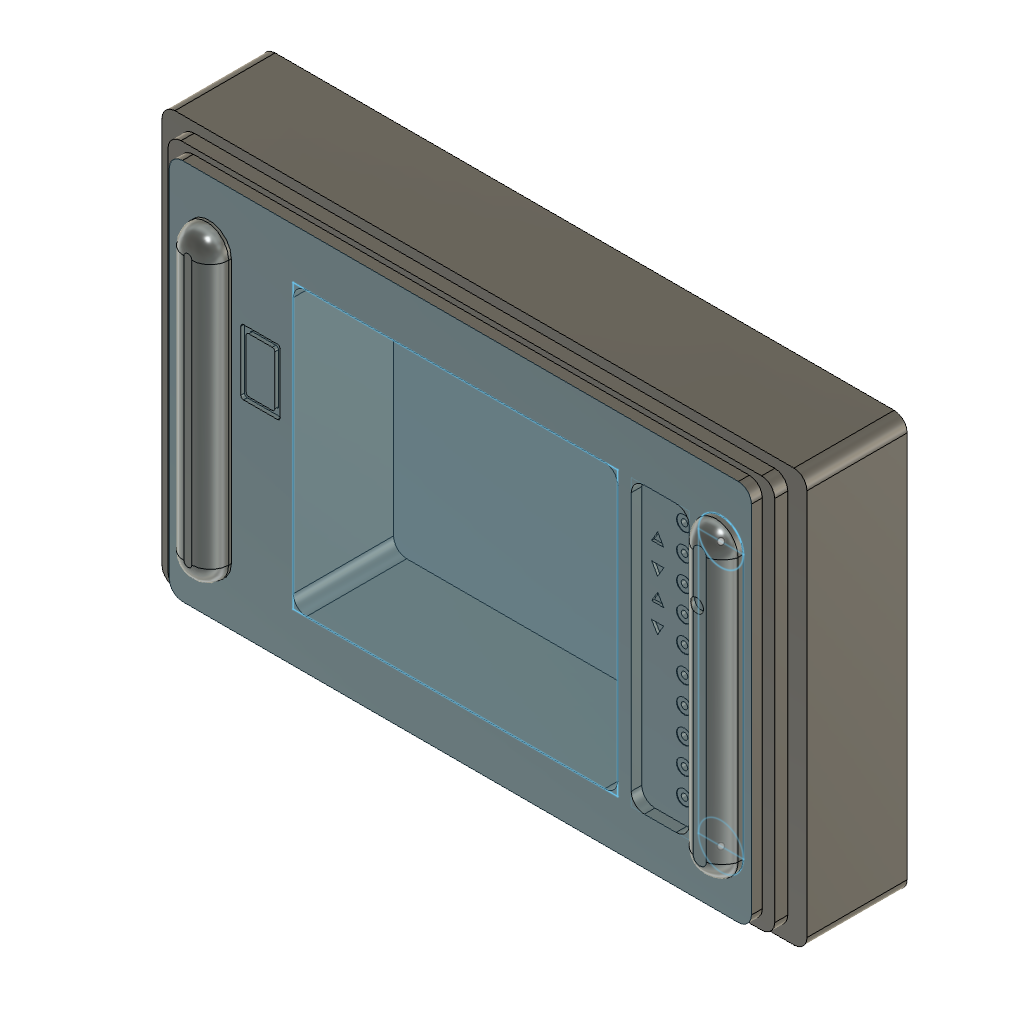
radar 5 (Autodesk Fusion 360 design; units mm, degrees)
part number: 2026-11-02-20-23-44-263
Autodesk Fusion 360 part; units mm, degrees
sketch "screen" plane through (0, 0, 0) normal (0, 1, 0) x (1, 0, 0)
  line L0 (-50.0347, -23.9941) -> (11.4653, -23.9941)
  line L1 (11.4653, -23.9941) -> (11.4653, 29.6059)
  line L2 (11.4653, 29.6059) -> (-50.0347, 29.6059)
  line L3 (-50.0347, 29.6059) -> (-50.0347, -23.9941)
  dimension "d1" = 61.5
  dimension "d2" = 53.6
  constraint horizontal L0
  constraint vertical L1
  constraint horizontal L2
  constraint vertical L3
  measures "d1" distance of L0.start L0.end
  measures "d2" distance of L0.start L2.end
sketch "shell" plane through (0, 0, 0) normal (0, 1, 0) x (-1, 0, 0)
  line L0 (86.0395, 43.9923) -> (-47.4605, 43.9923)
  line L1 (-47.4605, 43.9923) -> (-47.4605, -43.6077)
  line L2 (-47.4605, -43.6077) -> (86.0395, -43.6077)
  line L3 (86.0395, -43.6077) -> (86.0395, 43.9923)
  dimension "d3" = 133.5
  dimension "d4" = 87.6
  constraint horizontal L0
  constraint vertical L1
  constraint horizontal L2
  constraint vertical L3
  measures "d3" distance of L0.start L0.end
  measures "d4" distance of L0.start L2.end
extrude "Extrude1" add sketch "shell" along normal blind 2.5
sketch "1st shell extrude" plane through (0, 2.5, 0) normal (0, 1, 0) x (-1, 0, 0)
  line L0 (86.0395, -43.6077) -> (86.0395, 43.9923)
  line L1 (86.0395, 43.9923) -> (-47.4605, 43.9923)
  line L2 (-47.4605, 43.9923) -> (-47.4605, -43.6077)
  line L3 (-47.4605, -43.6077) -> (86.0395, -43.6077)
  line L4 (-50.2932, 45.2731) -> (88.8398, 45.2731)
  line L5 (88.8398, 45.2731) -> (88.8398, -44.9576)
  line L6 (88.8398, -44.9576) -> (-50.2932, -44.9576)
  line L7 (-50.2932, -44.9576) -> (-50.2932, 45.2731)
  constraint horizontal L4
  constraint vertical L5
  constraint horizontal L6
  constraint vertical L7
extrude "Extrude2" add sketch "1st shell extrude" along normal blind 3 contours L0 L1 L2 L3 | L4 L5 L6 L7
sketch "2nd shell extrude" plane through (0, 5.5, 0) normal (0, 1, 0) x (-1, 0, 0)
  line L0 (-50.2932, -44.9576) -> (88.8398, -44.9576)
  line L1 (88.8398, -44.9576) -> (88.8398, 45.2731)
  line L2 (88.8398, 45.2731) -> (-50.2932, 45.2731)
  line L3 (-50.2932, 45.2731) -> (-50.2932, -44.9576)
  line L4 (-54.7046, 47.5235) -> (93.2505, 47.5235)
  line L5 (93.2505, 47.5235) -> (93.2505, -47.2096)
  line L6 (93.2505, -47.2096) -> (-54.7046, -47.2096)
  line L7 (-54.7046, -47.2096) -> (-54.7046, 47.5235)
  constraint horizontal L4
  constraint vertical L5
  constraint horizontal L6
  constraint vertical L7
extrude "Extrude3" add sketch "2nd shell extrude" along normal blind 23 contours L0 L1 L2 L3 | L4 L5 L6 L7
fillet "Fillet1" radius 3 12 edges at (47.4605, 1.25, 43.9923) (50.2932, 4, 45.2731) (54.7046, 17, 47.5235) (54.7046, 17, -47.2096) (50.2932, 4, -44.9576) (47.4605, 1.25, -43.6077) (-86.0395, 1.25, 43.9923) (-88.8398, 4, 45.2731) (-93.2505, 17, 47.5235) (-93.2505, 17, -47.2096) (-88.8398, 4, -44.9576) (-86.0395, 1.25, -43.6077)
scale "Scale1" factor 0.826235 about (-83.0395, 0, 43.9923) bodies 1
move_body "Move1" bodies 1 to x (1, 0, 0) y (0, 1, 0) z (0, 0, 1) at (12, 0, -9.5)
move_body "Move2" bodies 1 to x (1, 0, 0) y (0, 1, 0) z (0, 0, 1) at (0, 0, -1)
extrude "Extrude11" cut sketch "screen" along normal blind 19
fillet "Fillet6" radius 2.5 4 edges at (-50.0347, 9.5, -29.6059) (11.4653, 9.5, -29.6059) (11.4653, 9.5, 23.9941) (-50.0347, 9.5, 23.9941)
sketch "Sketch16" plane through (0, 0, 0) normal (0, -1, 0) x (1, 0, 0)
  line L0 (8.9653, -29.6059) -> (-47.5347, -29.6059)
  arc A0 (-50.0347, -27.1059) -> (-47.5347, -29.6059) centre (-47.5347, -27.1059) ccw
  line L1 (-50.0347, -27.1059) -> (-50.0347, 21.4941)
  arc A1 (-47.5347, 23.9941) -> (-50.0347, 21.4941) centre (-47.5347, 21.4941) ccw
  line L2 (-47.5347, 23.9941) -> (8.9653, 23.9941)
  arc A2 (11.4653, 21.4941) -> (8.9653, 23.9941) centre (8.9653, 21.4941) ccw
  line L3 (11.4653, 21.4941) -> (11.4653, -27.1059)
  arc A3 (8.9653, -29.6059) -> (11.4653, -27.1059) centre (8.9653, -27.1059) ccw
  arc A4 (-73.5182, -36.4072) -> (-71.0395, -38.8859) centre (-71.0395, -36.4072) ccw
  line L4 (-71.0395, -38.8859) -> (34.3055, -38.8859)
  arc A5 (34.3055, -38.8859) -> (36.7842, -36.4072) centre (34.3055, -36.4072) ccw
  line L5 (36.7842, -36.4072) -> (36.7842, 31.0136)
  arc A6 (36.7842, 31.0136) -> (34.3055, 33.4923) centre (34.3055, 31.0136) ccw
  line L6 (34.3055, 33.4923) -> (-71.0395, 33.4923)
  arc A7 (-71.0395, 33.4923) -> (-73.5182, 31.0136) centre (-71.0395, 31.0136) ccw
  line L7 (-73.5182, 31.0136) -> (-73.5182, -36.4072)
  line L8 (14, 24) -> (25, 24)
  line L9 (25, 24) -> (25, -30)
  line L10 (25, -30) -> (14, -30)
  line L11 (14, -30) -> (14, 24)
  constraint horizontal L8
  constraint vertical L9
  constraint horizontal L10
  constraint vertical L11
extrude "Extrude12" cut sketch "Sketch16" against normal blind 2 contours L8 L9 L10 L11
sketch "Sketch17" plane through (0, 0, 0) normal (0, -1, 0) x (1, 0, 0)
  line L0 (25, 24) -> (25, -30)
  line L1 (25, -30) -> (14, -30)
  line L2 (14, -30) -> (14, 24)
  line L3 (14, 24) -> (25, 24)
  line L4 (8.9653, -29.6059) -> (-47.5347, -29.6059)
  arc A0 (-50.0347, -27.1059) -> (-47.5347, -29.6059) centre (-47.5347, -27.1059) ccw
  line L5 (-50.0347, -27.1059) -> (-50.0347, 21.4941)
  arc A1 (-47.5347, 23.9941) -> (-50.0347, 21.4941) centre (-47.5347, 21.4941) ccw
  line L6 (-47.5347, 23.9941) -> (8.9653, 23.9941)
  arc A2 (11.4653, 21.4941) -> (8.9653, 23.9941) centre (8.9653, 21.4941) ccw
  line L7 (11.4653, 21.4941) -> (11.4653, -27.1059)
  arc A3 (8.9653, -29.6059) -> (11.4653, -27.1059) centre (8.9653, -27.1059) ccw
  arc A4 (-73.5182, -36.4072) -> (-71.0395, -38.8859) centre (-71.0395, -36.4072) ccw
  line L8 (-71.0395, -38.8859) -> (34.3055, -38.8859)
  arc A5 (34.3055, -38.8859) -> (36.7842, -36.4072) centre (34.3055, -36.4072) ccw
  line L9 (36.7842, -36.4072) -> (36.7842, 31.0136)
  arc A6 (36.7842, 31.0136) -> (34.3055, 33.4923) centre (34.3055, 31.0136) ccw
  line L10 (34.3055, 33.4923) -> (-71.0395, 33.4923)
  arc A7 (-71.0395, 33.4923) -> (-73.5182, 31.0136) centre (-71.0395, 31.0136) ccw
  line L11 (-73.5182, 31.0136) -> (-73.5182, -36.4072)
  circle A8 centre (31, 22) radius 4.2426
  circle A9 centre (31, -28) radius 4.2426
  line L12 (26.7574, 22) -> (35.2426, 22)
  line L13 (35.2426, 22) -> (35.2426, -28)
  line L14 (35.2426, -28) -> (26.7574, -28)
  line L15 (26.7574, -28) -> (26.7574, 22)
  circle A10 centre (31, 22) radius 4.2426
  constraint horizontal L12
  constraint vertical L13
  constraint horizontal L14
  constraint vertical L15
  constraint coincident A9 L13.end
  constraint coincident A8 L12.start
  constraint concentric A8 A10
extrude "Extrude13" add sketch "Sketch17" along normal blind 4 contours A8 L12 A10 | A8 A9 L13 L15 A10 | A8 L12 A10 | A9 L14 | A9 L14
fillet "Fillet7" radius 3 tangency weight 0.49828 4 edges at (26.7574, -4, -3) (31, -4, -32.2426) (35.2426, -4, -3) (31, -4, 26.2426)
sketch "Sketch18" plane through (0, 0, 0) normal (0, -1, 0) x (1, 0, 0)
  line L0 (35.2426, 22) -> (35.2426, -28)
  arc A0 (26.7574, -28) -> (35.2426, -28) centre (31, -28) ccw
  line L1 (26.7574, -28) -> (26.7574, 22)
  arc A1 (35.2426, 22) -> (26.7574, 22) centre (31, 22) ccw
  line L2 (25, 24) -> (25, -30)
  line L3 (25, -30) -> (14, -30)
  line L4 (14, -30) -> (14, 24)
  line L5 (14, 24) -> (25, 24)
  line L6 (8.9653, -29.6059) -> (-47.5347, -29.6059)
  arc A2 (-50.0347, -27.1059) -> (-47.5347, -29.6059) centre (-47.5347, -27.1059) ccw
  line L7 (-50.0347, -27.1059) -> (-50.0347, 21.4941)
  arc A3 (-47.5347, 23.9941) -> (-50.0347, 21.4941) centre (-47.5347, 21.4941) ccw
  line L8 (-47.5347, 23.9941) -> (8.9653, 23.9941)
  arc A4 (11.4653, 21.4941) -> (8.9653, 23.9941) centre (8.9653, 21.4941) ccw
  line L9 (11.4653, 21.4941) -> (11.4653, -27.1059)
  arc A5 (8.9653, -29.6059) -> (11.4653, -27.1059) centre (8.9653, -27.1059) ccw
  arc A6 (-73.5182, -36.4072) -> (-71.0395, -38.8859) centre (-71.0395, -36.4072) ccw
  line L10 (-71.0395, -38.8859) -> (34.3055, -38.8859)
  arc A7 (34.3055, -38.8859) -> (36.7842, -36.4072) centre (34.3055, -36.4072) ccw
  line L11 (36.7842, -36.4072) -> (36.7842, 31.0136)
  arc A8 (36.7842, 31.0136) -> (34.3055, 33.4923) centre (34.3055, 31.0136) ccw
  line L12 (34.3055, 33.4923) -> (-71.0395, 33.4923)
  arc A9 (-71.0395, 33.4923) -> (-73.5182, 31.0136) centre (-71.0395, 31.0136) ccw
  line L13 (-73.5182, 31.0136) -> (-73.5182, -36.4072)
sketch "Sketch21" plane through (0, 0, 0) normal (0, -1, 0) x (1, 0, 0)
  circle A0 centre (-66, 22) radius 4.245
  circle A1 centre (-66, -28) radius 4.245
  line L0 (-70.245, 22) -> (-61.755, 22)
  line L1 (-61.755, 22) -> (-61.755, -28)
  line L2 (-61.755, -28) -> (-70.245, -28)
  line L3 (-70.245, -28) -> (-70.245, 22)
  dimension "d52" = 8.49
  dimension "d53" = 8.49
  constraint horizontal L0
  constraint vertical L1
  constraint horizontal L2
  constraint vertical L3
  constraint coincident A1 L1.end
  constraint coincident A0 L0.start
  measures "d52" diameter of A0
  measures "d53" diameter of A1
extrude "Extrude16" add sketch "Sketch21" along normal blind 4
fillet "Fillet8" radius 3.5 1 faces at (-64.585, -4, -11.3333)
fillet "Fillet9" radius 2.5 4 edges at (14, 1, 24) (25, 1, 24) (25, 1, -30) (14, 1, -30)
sketch "Sketch23" plane through (0, -4, 0) normal (0, -1, 0) x (1, 0, 0)
  line L0 (29.7574, -28) -> (29.7574, 22)
  spline S0 degree 3 poles (32.2426, -28) (32.2426, -28.263) (32.1575, -28.5224) (31.8527, -28.939) (31.6386, -29.0959) (31.1652, -29.2558) (30.9096, -29.2634) (30.4615, -29.1411) (30.2665, -29.0266) (29.9746, -28.7293) (29.8703, -28.5539) (29.776, -28.2474) (29.7574, -28.1243) (29.7574, -28) knots -5.389286 -5.389286 -5.389286 -5.389286 -5.310999 -5.310999 -5.235012 -5.235012 -5.161608 -5.161608 -5.096158 -5.096158 -5.036976 -5.036976 -4.999987 -4.999987 -4.999987 -4.999987
  line L1 (32.2426, 22) -> (32.2426, -28)
  spline S1 degree 3 poles (29.7574, 22) (29.7574, 22.2631) (29.8425, 22.5224) (30.1472, 22.9389) (30.3613, 23.0958) (30.8347, 23.2558) (31.0904, 23.2634) (31.5385, 23.1411) (31.7335, 23.0266) (32.0254, 22.7293) (32.1297, 22.5539) (32.224, 22.2474) (32.2426, 22.1243) (32.2426, 22) knots -10.778546 -10.778546 -10.778546 -10.778546 -10.700283 -10.700283 -10.624294 -10.624294 -10.550882 -10.550882 -10.485431 -10.485431 -10.426249 -10.426249 -10.38926 -10.38926 -10.38926 -10.38926
form "Form1" [no effect]
sketch "Sketch24" plane through (0, 0, 0) normal (0, -1, 0) x (1, 0, 0)
  line L0 (-59.9632, 12.3544) -> (-52.5208, 12.3544)
  line L1 (-52.5208, 12.3544) -> (-52.5208, 0)
  line L2 (-52.5208, 0) -> (-59.9632, 0)
  line L3 (-59.9632, 0) -> (-59.9632, 12.3544)
  constraint horizontal L0
  constraint vertical L1
  constraint horizontal L2
  constraint vertical L3
sketch "Sketch25" plane through (0, 0, 0) normal (0, -1, 0) x (1, 0, 0)
  line L0 (-59.5139, 11.756) -> (-52.9646, 11.756)
  line L1 (-52.9646, 11.756) -> (-52.9646, 0.5179)
  line L2 (-52.9646, 0.5179) -> (-59.5139, 0.5179)
  line L3 (-59.5139, 0.5179) -> (-59.5139, 11.756)
  constraint horizontal L0
  constraint vertical L1
  constraint horizontal L2
  constraint vertical L3
extrude "Extrude17" cut sketch "Sketch24" against normal blind 0.7 thin wall 1 inside
fillet "Fillet10" radius 0.5 4 edges at (-53.5208, 0.35, 11.3544) (-53.5208, 0.35, 1) (-58.9632, 0.35, 11.3544) (-58.9632, 0.35, 1)
fillet "Fillet11" radius 0.5 4 edges at (-59.9632, 0.35, 12.3544) (-52.5208, 0.35, 0) (-52.5208, 0.35, 12.3544) (-59.9632, 0.35, 0)
sketch "Sketch26" plane through (0, 0, 0) normal (0, -1, 0) x (1, 0, 0)
  circle A0 through (23.4142, 19.5, 1) (21.2929, 20.7247, 1) (21.2929, 18.2753, 1)
  circle A1 through (23.4142, 14.5, 1) (21.2929, 15.7247, 1) (21.2929, 13.2753, 1)
  circle A2 through (23.4142, 9.5, 1) (21.2929, 10.7247, 1) (21.2929, 8.2753, 1)
  circle A3 through (23.4142, 4.5, 1) (21.2929, 5.7247, 1) (21.2929, 3.2753, 1)
  circle A4 through (23.4142, -0.5, 1) (21.2929, 0.7247, 1) (21.2929, -1.7247, 1)
  circle A5 through (23.4142, -5.5, 1) (21.2929, -4.2753, 1) (21.2929, -6.7247, 1)
  circle A6 through (23.4142, -10.5, 1) (21.2929, -9.2753, 1) (21.2929, -11.7247, 1)
  circle A7 through (23.4142, -15.5, 1) (21.2929, -14.2753, 1) (21.2929, -16.7247, 1)
  circle A8 through (23.4142, -25.5, 1) (21.2929, -24.2753, 1) (21.2929, -26.7247, 1)
  circle A9 through (23.4142, -20.5, 1) (21.2929, -19.2753, 1) (21.2929, -21.7247, 1)
  circle A10 through (22.615, 19.5, 1) (21.6925, 20.0326, 1) (21.6925, 18.9674, 1)
  circle A11 through (22.615, 14.5, 1) (21.6925, 15.0326, 1) (21.6925, 13.9674, 1)
  circle A12 through (22.615, 9.5, 1) (21.6925, 10.0326, 1) (21.6925, 8.9674, 1)
  circle A13 through (22.615, 4.5, 1) (21.6925, 5.0326, 1) (21.6925, 3.9674, 1)
  circle A14 through (22.615, -0.5, 1) (21.6925, 0.0326, 1) (21.6925, -1.0326, 1)
  circle A15 through (22.615, -5.5, 1) (21.6925, -4.9674, 1) (21.6925, -6.0326, 1)
  circle A16 through (22.615, -10.5, 1) (21.6925, -9.9674, 1) (21.6925, -11.0326, 1)
  circle A17 through (22.615, -15.5, 1) (21.6925, -14.9674, 1) (21.6925, -16.0326, 1)
  circle A18 through (22.615, -20.5, 1) (21.6925, -19.9674, 1) (21.6925, -21.0326, 1)
  circle A19 through (22.615, -25.5, 1) (21.6925, -24.9674, 1) (21.6925, -26.0326, 1)
  dimension "d67" = 1.23
  dimension "d68" = 1.23
  dimension "d69" = 1.23
  dimension "d70" = 1.23
  dimension "d71" = 1.23
  dimension "d72" = 1.23
  dimension "d73" = 1.23
  dimension "d74" = 1.23
  dimension "d75" = 1.23
  dimension "d76" = 1.23
sketch "Sketch27" plane through (0, -4, 0) normal (0, -1, 0) x (1, 0, 0)
  circle A0 centre (30.5778, 15.4337) radius 1.2151
  circle A1 centre (30.5778, 19.4337) radius 1.2151
sketch "Sketch28" plane through (0, 0, 0) normal (0, 0, 1) x (1, 0, 0)
extrude "Extrude19" cut sketch "Sketch26" against normal blind 4 contours A10 | A11 | A12 | A13 | A14 | A15 | A16 | A17 | A18 | A19 in plane through (0, -1, 0) normal (0, -1, 0)
extrude "Extrude20" cut sketch "Sketch26" against normal blind 3.1 contours A0 | A1 | A2 | A3 | A4 | A5 | A6 | A7 | A8 | A9 in plane through (0, -1, 0) normal (0, -1, 0)
sketch "Sketch30" plane through (0, 0, 0) normal (0, -1, 0) x (1, 0, 0)
  line L0 (18.1572, 3.7185) -> (17.0186, 5.6907)
  line L1 (17.0186, 5.6907) -> (15.8799, 3.7185)
  line L2 (15.8799, 3.7185) -> (18.1572, 3.7185)
  line L3 (18.1572, 13.6185) -> (17.0186, 15.5907)
  line L4 (15.8799, 13.6185) -> (18.1572, 13.6185)
  line L5 (17.0186, 15.5907) -> (15.8799, 13.6185)
  line L6 (15.848, 0.6445) -> (17.0179, -1.3199)
  line L7 (17.0179, -1.3199) -> (18.1341, 0.6754)
  line L8 (18.1341, 0.6754) -> (15.848, 0.6445)
  line L9 (17.0179, -1.3199) -> (18.1341, 0.6754)
  line L10 (15.848, 0.6445) -> (17.0179, -1.3199)
  line L11 (18.1341, 0.6754) -> (15.848, 0.6445)
  line L12 (16.997, 8.2892) -> (18.1724, 10.2502)
  line L13 (18.1724, 10.2502) -> (15.8864, 10.2876)
  line L14 (15.8864, 10.2876) -> (16.997, 8.2892)
  point P0 (17.0186, 4.3759)
  point P1 (17.0186, 14.2759)
  point P2 (17, 0)
  point P3 (17, 0)
  point P4 (17.0186, 9.609)
  dimension "d83" = 0.66
  dimension "d84" = 0.66
  measures "d83" distance of P3 L8
  measures "d84" distance of P4 L14
extrude "Extrude21" cut sketch "Sketch30" against normal blind 2.5
sketch "Sketch31" plane through (0, 0, 0) normal (0, -1, 0) x (1, 0, 0)
  circle A0 through (30.4431, 14.4831, 4.0396) (29.2922, 12.5803, 4.0665) (31.5151, 12.5347, 4.0127)
extrude "Extrude22" cut sketch "Sketch31" against normal blind 1 contours A0 in plane through (0.1151, -4.7651, -0.0024) normal (0.024152, -0.999708, -0.000495)
